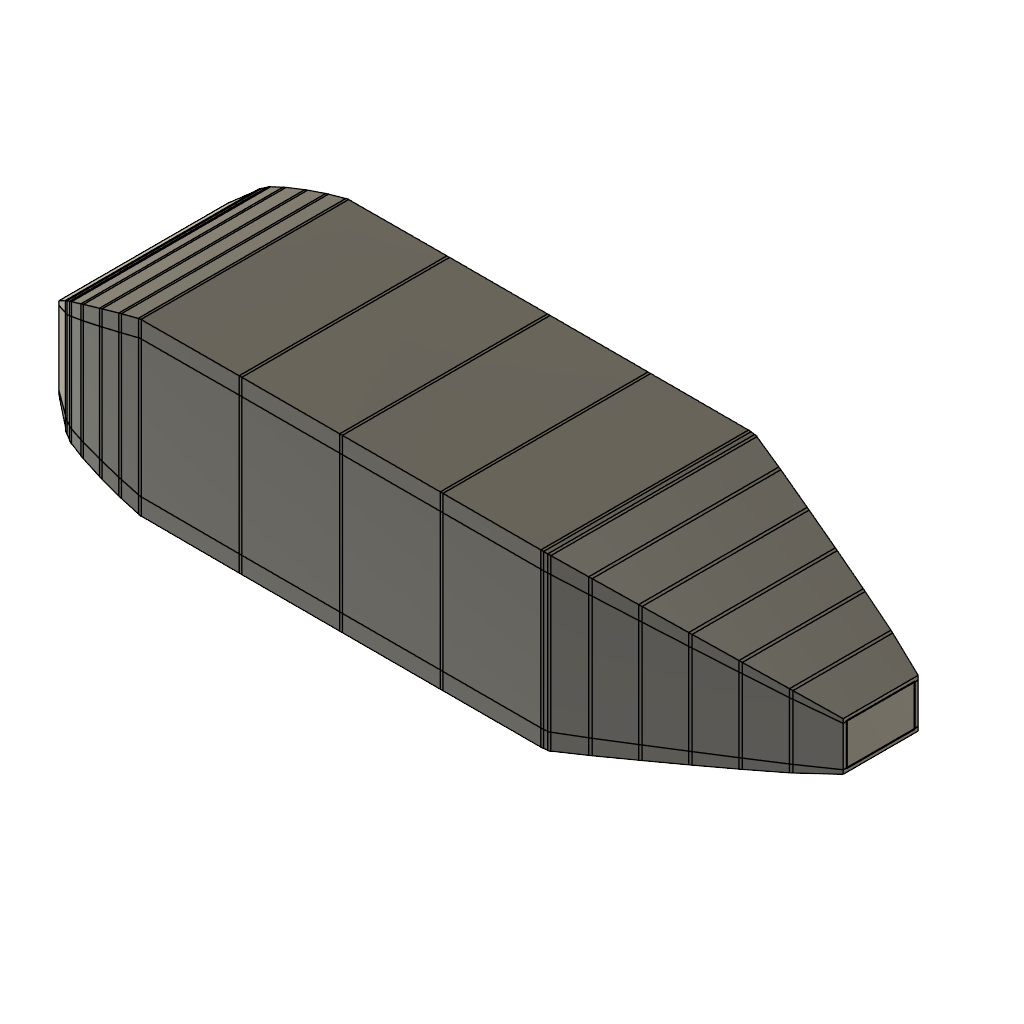
Magnetide-B-full (Autodesk Fusion 360 design; units mm, degrees)
part number: 2026-10-21-01-34-00-853
Autodesk Fusion 360 part; units mm, degrees
(part 1 of 3)
ref_plane "WorkPlane1" through (60, 0, 0) normal (1, 0, 0) x (0, 1, 0)
sketch "plate_a" plane through (60, 0, 0) normal (1, 0, 0) x (0, 0, -1)
  line L0 (-7, -21.85) -> (-7, 21.85)
  line L1 (-7, 21.85) -> (-10.5, 21.85)
  line L2 (-10.5, 21.85) -> (-10.5, 22.75)
  line L3 (-10.5, 22.75) -> (-7, 22.75)
  line L4 (-7, 22.75) -> (-7, 23.5)
  line L5 (-7, 23.5) -> (-18.5, 23.5)
  line L6 (-18.5, 23.5) -> (-18.5, 20.3)
  line L7 (-18.5, 20.3) -> (-8.5, 20.3)
  line L8 (-8.5, 20.3) -> (-8.5, -20.3)
  line L9 (-8.5, -20.3) -> (-18.5, -20.3)
  line L10 (-18.5, -20.3) -> (-18.5, -23.5)
  line L11 (-18.5, -23.5) -> (-7, -23.5)
  line L12 (-7, -23.5) -> (-7, -22.75)
  line L13 (-7, -22.75) -> (-10.5, -22.75)
  line L14 (-10.5, -22.75) -> (-10.5, -21.85)
  line L15 (-10.5, -21.85) -> (-7, -21.85)
extrude "Extrude1" add sketch "plate_a" along normal mid plane 120 makes body 1
ref_plane "WorkPlane2" through (60, 0, 0) normal (1, 0, 0) x (0, 1, 0)
sketch "plate_b" plane through (60, 0, 0) normal (1, 0, 0) x (0, 0, -1)
  line L0 (7, -21.85) -> (7, 21.85)
  line L1 (7, 21.85) -> (10.5, 21.85)
  line L2 (10.5, 21.85) -> (10.5, 22.75)
  line L3 (10.5, 22.75) -> (7, 22.75)
  line L4 (7, 22.75) -> (7, 23.5)
  line L5 (7, 23.5) -> (18.5, 23.5)
  line L6 (18.5, 23.5) -> (18.5, 20.3)
  line L7 (18.5, 20.3) -> (8.5, 20.3)
  line L8 (8.5, 20.3) -> (8.5, -20.3)
  line L9 (8.5, -20.3) -> (18.5, -20.3)
  line L10 (18.5, -20.3) -> (18.5, -23.5)
  line L11 (18.5, -23.5) -> (7, -23.5)
  line L12 (7, -23.5) -> (7, -22.75)
  line L13 (7, -22.75) -> (10.5, -22.75)
  line L14 (10.5, -22.75) -> (10.5, -21.85)
  line L15 (10.5, -21.85) -> (7, -21.85)
extrude "Extrude2" add sketch "plate_b" along normal mid plane 120 separate body makes body 2
ref_plane "WorkPlane3" through (0, -22.7, 0) normal (0, 1, 0) x (0, 0, 1)
sketch "rail_left" plane through (0, -22.7, 0) normal (0, 1, 0) x (1, 0, 0)
  line L0 (0, 7) -> (120, 7)
  line L1 (120, 7) -> (120, -7)
  line L2 (120, -7) -> (0, -7)
  line L3 (0, -7) -> (0, 7)
extrude "Extrude3" add sketch "rail_left" along normal mid plane 1.6 separate body makes body 3
ref_plane "WorkPlane4" through (0, 22.7, 0) normal (0, 1, 0) x (0, 0, 1)
sketch "rail_right" plane through (0, 22.7, 0) normal (0, 1, 0) x (1, 0, 0)
  line L0 (0, 7) -> (120, 7)
  line L1 (120, 7) -> (120, -7)
  line L2 (120, -7) -> (0, -7)
  line L3 (0, -7) -> (0, 7)
extrude "Extrude4" add sketch "rail_right" along normal mid plane 1.6 separate body makes body 4
ref_plane "WorkPlane5" through (-20, 0, 0) normal (1, 0, 0) x (0, 1, 0)
sketch "Sketch5" plane through (-20, 0, 0) normal (1, 0, 0) x (0, 0, -1)
  line L0 (-12, -23.5) -> (-10.5, -23.5)
  line L1 (-10.5, -23.5) -> (-10.5, 23.5)
  line L2 (-10.5, 23.5) -> (-12, 23.5)
  line L3 (-12, 23.5) -> (-12, -23.5)
ref_plane "WorkPlane6" through (-15.6, 0, 0) normal (1, 0, 0) x (0, 1, 0)
sketch "Sketch6" plane through (-15.6, 0, 0) normal (1, 0, 0) x (0, 0, -1)
  line L0 (-10.6294, -23.5) -> (-9.1294, -23.5)
  line L1 (-9.1294, -23.5) -> (-9.1294, 23.5)
  line L2 (-9.1294, 23.5) -> (-10.6294, 23.5)
  line L3 (-10.6294, 23.5) -> (-10.6294, -23.5)
loft "Loft1" add profiles "Sketch5", "Sketch6" section 1 section 2 separate body makes body 5
ref_plane "WorkPlane7" through (-16.4, 0, 0) normal (1, 0, 0) x (0, 1, 0)
sketch "Sketch7" plane through (-16.4, 0, 0) normal (1, 0, 0) x (0, 0, -1)
  line L0 (-10.8534, -23.5) -> (-9.3534, -23.5)
  line L1 (-9.3534, -23.5) -> (-9.3534, 23.5)
  line L2 (-9.3534, 23.5) -> (-10.8534, 23.5)
  line L3 (-10.8534, 23.5) -> (-10.8534, -23.5)
ref_plane "WorkPlane8" through (-11.6, 0, 0) normal (1, 0, 0) x (0, 1, 0)
sketch "Sketch8" plane through (-11.6, 0, 0) normal (1, 0, 0) x (0, 0, -1)
  line L0 (-9.6774, -23.5) -> (-8.1774, -23.5)
  line L1 (-8.1774, -23.5) -> (-8.1774, 23.5)
  line L2 (-8.1774, 23.5) -> (-9.6774, 23.5)
  line L3 (-9.6774, 23.5) -> (-9.6774, -23.5)
loft "Loft2" add profiles "Sketch7", "Sketch8" section 1 section 2 separate body makes body 6
ref_plane "WorkPlane9" through (-12.4, 0, 0) normal (1, 0, 0) x (0, 1, 0)
sketch "Sketch9" plane through (-12.4, 0, 0) normal (1, 0, 0) x (0, 0, -1)
  line L0 (-9.8454, -23.5) -> (-8.3454, -23.5)
  line L1 (-8.3454, -23.5) -> (-8.3454, 23.5)
  line L2 (-8.3454, 23.5) -> (-9.8454, 23.5)
  line L3 (-9.8454, 23.5) -> (-9.8454, -23.5)
ref_plane "WorkPlane10" through (-7.6, 0, 0) normal (1, 0, 0) x (0, 1, 0)
sketch "Sketch10" plane through (-7.6, 0, 0) normal (1, 0, 0) x (0, 0, -1)
  line L0 (-9.0054, -23.5) -> (-7.5054, -23.5)
  line L1 (-7.5054, -23.5) -> (-7.5054, 23.5)
  line L2 (-7.5054, 23.5) -> (-9.0054, 23.5)
  line L3 (-9.0054, 23.5) -> (-9.0054, -23.5)
loft "Loft3" add profiles "Sketch9", "Sketch10" section 1 section 2 separate body makes body 7
ref_plane "WorkPlane11" through (-8.4, 0, 0) normal (1, 0, 0) x (0, 1, 0)
sketch "Sketch11" plane through (-8.4, 0, 0) normal (1, 0, 0) x (0, 0, -1)
  line L0 (-9.1174, -23.5) -> (-7.6174, -23.5)
  line L1 (-7.6174, -23.5) -> (-7.6174, 23.5)
  line L2 (-7.6174, 23.5) -> (-9.1174, 23.5)
  line L3 (-9.1174, 23.5) -> (-9.1174, -23.5)
ref_plane "WorkPlane12" through (-3.6, 0, 0) normal (1, 0, 0) x (0, 1, 0)
sketch "Sketch12" plane through (-3.6, 0, 0) normal (1, 0, 0) x (0, 0, -1)
  line L0 (-8.6134, -23.5) -> (-7.1134, -23.5)
  line L1 (-7.1134, -23.5) -> (-7.1134, 23.5)
  line L2 (-7.1134, 23.5) -> (-8.6134, 23.5)
  line L3 (-8.6134, 23.5) -> (-8.6134, -23.5)
loft "Loft4" add profiles "Sketch11", "Sketch12" section 1 section 2 separate body makes body 8
ref_plane "WorkPlane13" through (-4.4, 0, 0) normal (1, 0, 0) x (0, 1, 0)
sketch "Sketch13" plane through (-4.4, 0, 0) normal (1, 0, 0) x (0, 0, -1)
  line L0 (-8.6694, -23.5) -> (-7.1694, -23.5)
  line L1 (-7.1694, -23.5) -> (-7.1694, 23.5)
  line L2 (-7.1694, 23.5) -> (-8.6694, 23.5)
  line L3 (-8.6694, 23.5) -> (-8.6694, -23.5)
ref_plane "WorkPlane14" through (0, 0, 0) normal (1, 0, 0) x (0, 1, 0)
sketch "Sketch14" plane through (0, 0, 0) normal (1, 0, 0) x (0, 0, -1)
  line L0 (-8.5, -23.5) -> (-7, -23.5)
  line L1 (-7, -23.5) -> (-7, 23.5)
  line L2 (-7, 23.5) -> (-8.5, 23.5)
  line L3 (-8.5, 23.5) -> (-8.5, -23.5)
loft "Loft5" add profiles "Sketch13", "Sketch14" section 1 section 2 separate body makes body 9
ref_plane "WorkPlane15" through (-20, 0, 0) normal (1, 0, 0) x (0, 1, 0)
sketch "Sketch15" plane through (-20, 0, 0) normal (1, 0, 0) x (0, 0, -1)
  line L0 (10.5, -23.5) -> (12, -23.5)
  line L1 (12, -23.5) -> (12, 23.5)
  line L2 (12, 23.5) -> (10.5, 23.5)
  line L3 (10.5, 23.5) -> (10.5, -23.5)
ref_plane "WorkPlane16" through (-15.6, 0, 0) normal (1, 0, 0) x (0, 1, 0)
sketch "Sketch16" plane through (-15.6, 0, 0) normal (1, 0, 0) x (0, 0, -1)
  line L0 (9.1294, -23.5) -> (10.6294, -23.5)
  line L1 (10.6294, -23.5) -> (10.6294, 23.5)
  line L2 (10.6294, 23.5) -> (9.1294, 23.5)
  line L3 (9.1294, 23.5) -> (9.1294, -23.5)
loft "Loft6" add profiles "Sketch15", "Sketch16" section 1 section 2 separate body makes body 10
ref_plane "WorkPlane17" through (-16.4, 0, 0) normal (1, 0, 0) x (0, 1, 0)
sketch "Sketch17" plane through (-16.4, 0, 0) normal (1, 0, 0) x (0, 0, -1)
  line L0 (9.3534, -23.5) -> (10.8534, -23.5)
  line L1 (10.8534, -23.5) -> (10.8534, 23.5)
  line L2 (10.8534, 23.5) -> (9.3534, 23.5)
  line L3 (9.3534, 23.5) -> (9.3534, -23.5)
ref_plane "WorkPlane18" through (-11.6, 0, 0) normal (1, 0, 0) x (0, 1, 0)
sketch "Sketch18" plane through (-11.6, 0, 0) normal (1, 0, 0) x (0, 0, -1)
  line L0 (8.1774, -23.5) -> (9.6774, -23.5)
  line L1 (9.6774, -23.5) -> (9.6774, 23.5)
  line L2 (9.6774, 23.5) -> (8.1774, 23.5)
  line L3 (8.1774, 23.5) -> (8.1774, -23.5)
loft "Loft7" add profiles "Sketch17", "Sketch18" section 1 section 2 separate body makes body 11
ref_plane "WorkPlane19" through (-12.4, 0, 0) normal (1, 0, 0) x (0, 1, 0)
sketch "Sketch19" plane through (-12.4, 0, 0) normal (1, 0, 0) x (0, 0, -1)
  line L0 (8.3454, -23.5) -> (9.8454, -23.5)
  line L1 (9.8454, -23.5) -> (9.8454, 23.5)
  line L2 (9.8454, 23.5) -> (8.3454, 23.5)
  line L3 (8.3454, 23.5) -> (8.3454, -23.5)
ref_plane "WorkPlane20" through (-7.6, 0, 0) normal (1, 0, 0) x (0, 1, 0)
sketch "Sketch20" plane through (-7.6, 0, 0) normal (1, 0, 0) x (0, 0, -1)
  line L0 (7.5054, -23.5) -> (9.0054, -23.5)
  line L1 (9.0054, -23.5) -> (9.0054, 23.5)
  line L2 (9.0054, 23.5) -> (7.5054, 23.5)
  line L3 (7.5054, 23.5) -> (7.5054, -23.5)
loft "Loft8" add profiles "Sketch19", "Sketch20" section 1 section 2 separate body makes body 12
ref_plane "WorkPlane21" through (-8.4, 0, 0) normal (1, 0, 0) x (0, 1, 0)
sketch "Sketch21" plane through (-8.4, 0, 0) normal (1, 0, 0) x (0, 0, -1)
  line L0 (7.6174, -23.5) -> (9.1174, -23.5)
  line L1 (9.1174, -23.5) -> (9.1174, 23.5)
  line L2 (9.1174, 23.5) -> (7.6174, 23.5)
  line L3 (7.6174, 23.5) -> (7.6174, -23.5)
ref_plane "WorkPlane22" through (-3.6, 0, 0) normal (1, 0, 0) x (0, 1, 0)
sketch "Sketch22" plane through (-3.6, 0, 0) normal (1, 0, 0) x (0, 0, -1)
  line L0 (7.1134, -23.5) -> (8.6134, -23.5)
  line L1 (8.6134, -23.5) -> (8.6134, 23.5)
  line L2 (8.6134, 23.5) -> (7.1134, 23.5)
  line L3 (7.1134, 23.5) -> (7.1134, -23.5)
loft "Loft9" add profiles "Sketch21", "Sketch22" section 1 section 2 separate body makes body 13
ref_plane "WorkPlane23" through (-4.4, 0, 0) normal (1, 0, 0) x (0, 1, 0)
sketch "Sketch23" plane through (-4.4, 0, 0) normal (1, 0, 0) x (0, 0, -1)
  line L0 (7.1694, -23.5) -> (8.6694, -23.5)
  line L1 (8.6694, -23.5) -> (8.6694, 23.5)
  line L2 (8.6694, 23.5) -> (7.1694, 23.5)
  line L3 (7.1694, 23.5) -> (7.1694, -23.5)
ref_plane "WorkPlane24" through (0, 0, 0) normal (1, 0, 0) x (0, 1, 0)
sketch "Sketch24" plane through (0, 0, 0) normal (1, 0, 0) x (0, 0, -1)
  line L0 (7, -23.5) -> (8.5, -23.5)
  line L1 (8.5, -23.5) -> (8.5, 23.5)
  line L2 (8.5, 23.5) -> (7, 23.5)
  line L3 (7, 23.5) -> (7, -23.5)
loft "Loft10" add profiles "Sketch23", "Sketch24" section 1 section 2 separate body makes body 14
ref_plane "WorkPlane25" through (-20, 0, 0) normal (1, 0, 0) x (0, 1, 0)
sketch "Sketch25" plane through (-20, 0, 0) normal (1, 0, 0) x (0, 0, -1)
  line L0 (-10.5, -23.5) -> (10.5, -23.5)
  line L1 (10.5, -23.5) -> (10.5, -21.5)
  line L2 (10.5, -21.5) -> (-10.5, -21.5)
  line L3 (-10.5, -21.5) -> (-10.5, -23.5)
ref_plane "WorkPlane26" through (-15.6, 0, 0) normal (1, 0, 0) x (0, 1, 0)
sketch "Sketch26" plane through (-15.6, 0, 0) normal (1, 0, 0) x (0, 0, -1)
  line L0 (-9.1294, -23.5) -> (9.1294, -23.5)
  line L1 (9.1294, -23.5) -> (9.1294, -21.5)
  line L2 (9.1294, -21.5) -> (-9.1294, -21.5)
  line L3 (-9.1294, -21.5) -> (-9.1294, -23.5)
loft "Loft11" add profiles "Sketch25", "Sketch26" section 1 section 2 separate body makes body 15
ref_plane "WorkPlane27" through (-16.4, 0, 0) normal (1, 0, 0) x (0, 1, 0)
sketch "Sketch27" plane through (-16.4, 0, 0) normal (1, 0, 0) x (0, 0, -1)
  line L0 (-9.3534, -23.5) -> (9.3534, -23.5)
  line L1 (9.3534, -23.5) -> (9.3534, -21.5)
  line L2 (9.3534, -21.5) -> (-9.3534, -21.5)
  line L3 (-9.3534, -21.5) -> (-9.3534, -23.5)
ref_plane "WorkPlane28" through (-11.6, 0, 0) normal (1, 0, 0) x (0, 1, 0)
sketch "Sketch28" plane through (-11.6, 0, 0) normal (1, 0, 0) x (0, 0, -1)
  line L0 (-8.1774, -23.5) -> (8.1774, -23.5)
  line L1 (8.1774, -23.5) -> (8.1774, -21.5)
  line L2 (8.1774, -21.5) -> (-8.1774, -21.5)
  line L3 (-8.1774, -21.5) -> (-8.1774, -23.5)
loft "Loft12" add profiles "Sketch27", "Sketch28" section 1 section 2 separate body makes body 16
ref_plane "WorkPlane29" through (-12.4, 0, 0) normal (1, 0, 0) x (0, 1, 0)
sketch "Sketch29" plane through (-12.4, 0, 0) normal (1, 0, 0) x (0, 0, -1)
  line L0 (-8.3454, -23.5) -> (8.3454, -23.5)
  line L1 (8.3454, -23.5) -> (8.3454, -21.5)
  line L2 (8.3454, -21.5) -> (-8.3454, -21.5)
  line L3 (-8.3454, -21.5) -> (-8.3454, -23.5)
ref_plane "WorkPlane30" through (-7.6, 0, 0) normal (1, 0, 0) x (0, 1, 0)
sketch "Sketch30" plane through (-7.6, 0, 0) normal (1, 0, 0) x (0, 0, -1)
  line L0 (-7.5054, -23.5) -> (7.5054, -23.5)
  line L1 (7.5054, -23.5) -> (7.5054, -21.5)
  line L2 (7.5054, -21.5) -> (-7.5054, -21.5)
  line L3 (-7.5054, -21.5) -> (-7.5054, -23.5)
loft "Loft13" add profiles "Sketch29", "Sketch30" section 1 section 2 separate body makes body 17
ref_plane "WorkPlane31" through (-8.4, 0, 0) normal (1, 0, 0) x (0, 1, 0)
sketch "Sketch31" plane through (-8.4, 0, 0) normal (1, 0, 0) x (0, 0, -1)
  line L0 (-7.6174, -23.5) -> (7.6174, -23.5)
  line L1 (7.6174, -23.5) -> (7.6174, -21.5)
  line L2 (7.6174, -21.5) -> (-7.6174, -21.5)
  line L3 (-7.6174, -21.5) -> (-7.6174, -23.5)
ref_plane "WorkPlane32" through (-3.6, 0, 0) normal (1, 0, 0) x (0, 1, 0)
sketch "Sketch32" plane through (-3.6, 0, 0) normal (1, 0, 0) x (0, 0, -1)
  line L0 (-7.1134, -23.5) -> (7.1134, -23.5)
  line L1 (7.1134, -23.5) -> (7.1134, -21.5)
  line L2 (7.1134, -21.5) -> (-7.1134, -21.5)
  line L3 (-7.1134, -21.5) -> (-7.1134, -23.5)
loft "Loft14" add profiles "Sketch31", "Sketch32" section 1 section 2 separate body makes body 18
ref_plane "WorkPlane33" through (-4.4, 0, 0) normal (1, 0, 0) x (0, 1, 0)
sketch "Sketch33" plane through (-4.4, 0, 0) normal (1, 0, 0) x (0, 0, -1)
  line L0 (-7.1694, -23.5) -> (7.1694, -23.5)
  line L1 (7.1694, -23.5) -> (7.1694, -21.5)
  line L2 (7.1694, -21.5) -> (-7.1694, -21.5)
  line L3 (-7.1694, -21.5) -> (-7.1694, -23.5)
ref_plane "WorkPlane34" through (0, 0, 0) normal (1, 0, 0) x (0, 1, 0)
sketch "Sketch34" plane through (0, 0, 0) normal (1, 0, 0) x (0, 0, -1)
  line L0 (-7, -23.5) -> (7, -23.5)
  line L1 (7, -23.5) -> (7, -21.5)
  line L2 (7, -21.5) -> (-7, -21.5)
  line L3 (-7, -21.5) -> (-7, -23.5)
loft "Loft15" add profiles "Sketch33", "Sketch34" section 1 section 2 separate body makes body 19
ref_plane "WorkPlane35" through (-20, 0, 0) normal (1, 0, 0) x (0, 1, 0)
sketch "Sketch35" plane through (-20, 0, 0) normal (1, 0, 0) x (0, 0, -1)
  line L0 (-10.5, 21.5) -> (10.5, 21.5)
  line L1 (10.5, 21.5) -> (10.5, 23.5)
  line L2 (10.5, 23.5) -> (-10.5, 23.5)
  line L3 (-10.5, 23.5) -> (-10.5, 21.5)
ref_plane "WorkPlane36" through (-15.6, 0, 0) normal (1, 0, 0) x (0, 1, 0)
sketch "Sketch36" plane through (-15.6, 0, 0) normal (1, 0, 0) x (0, 0, -1)
  line L0 (-9.1294, 21.5) -> (9.1294, 21.5)
  line L1 (9.1294, 21.5) -> (9.1294, 23.5)
  line L2 (9.1294, 23.5) -> (-9.1294, 23.5)
  line L3 (-9.1294, 23.5) -> (-9.1294, 21.5)
loft "Loft16" add profiles "Sketch35", "Sketch36" section 1 section 2 separate body makes body 20
ref_plane "WorkPlane37" through (-16.4, 0, 0) normal (1, 0, 0) x (0, 1, 0)
sketch "Sketch37" plane through (-16.4, 0, 0) normal (1, 0, 0) x (0, 0, -1)
  line L0 (-9.3534, 21.5) -> (9.3534, 21.5)
  line L1 (9.3534, 21.5) -> (9.3534, 23.5)
  line L2 (9.3534, 23.5) -> (-9.3534, 23.5)
  line L3 (-9.3534, 23.5) -> (-9.3534, 21.5)
ref_plane "WorkPlane38" through (-11.6, 0, 0) normal (1, 0, 0) x (0, 1, 0)
sketch "Sketch38" plane through (-11.6, 0, 0) normal (1, 0, 0) x (0, 0, -1)
  line L0 (-8.1774, 21.5) -> (8.1774, 21.5)
  line L1 (8.1774, 21.5) -> (8.1774, 23.5)
  line L2 (8.1774, 23.5) -> (-8.1774, 23.5)
  line L3 (-8.1774, 23.5) -> (-8.1774, 21.5)
loft "Loft17" add profiles "Sketch37", "Sketch38" section 1 section 2 separate body makes body 21
ref_plane "WorkPlane39" through (-12.4, 0, 0) normal (1, 0, 0) x (0, 1, 0)
sketch "Sketch39" plane through (-12.4, 0, 0) normal (1, 0, 0) x (0, 0, -1)
  line L0 (-8.3454, 21.5) -> (8.3454, 21.5)
  line L1 (8.3454, 21.5) -> (8.3454, 23.5)
  line L2 (8.3454, 23.5) -> (-8.3454, 23.5)
  line L3 (-8.3454, 23.5) -> (-8.3454, 21.5)
ref_plane "WorkPlane40" through (-7.6, 0, 0) normal (1, 0, 0) x (0, 1, 0)
sketch "Sketch40" plane through (-7.6, 0, 0) normal (1, 0, 0) x (0, 0, -1)
  line L0 (-7.5054, 21.5) -> (7.5054, 21.5)
  line L1 (7.5054, 21.5) -> (7.5054, 23.5)
  line L2 (7.5054, 23.5) -> (-7.5054, 23.5)
  line L3 (-7.5054, 23.5) -> (-7.5054, 21.5)
loft "Loft18" add profiles "Sketch39", "Sketch40" section 1 section 2 separate body makes body 22
ref_plane "WorkPlane41" through (-8.4, 0, 0) normal (1, 0, 0) x (0, 1, 0)
sketch "Sketch41" plane through (-8.4, 0, 0) normal (1, 0, 0) x (0, 0, -1)
  line L0 (-7.6174, 21.5) -> (7.6174, 21.5)
  line L1 (7.6174, 21.5) -> (7.6174, 23.5)
  line L2 (7.6174, 23.5) -> (-7.6174, 23.5)
  line L3 (-7.6174, 23.5) -> (-7.6174, 21.5)
ref_plane "WorkPlane42" through (-3.6, 0, 0) normal (1, 0, 0) x (0, 1, 0)
sketch "Sketch42" plane through (-3.6, 0, 0) normal (1, 0, 0) x (0, 0, -1)
  line L0 (-7.1134, 21.5) -> (7.1134, 21.5)
  line L1 (7.1134, 21.5) -> (7.1134, 23.5)
  line L2 (7.1134, 23.5) -> (-7.1134, 23.5)
  line L3 (-7.1134, 23.5) -> (-7.1134, 21.5)
loft "Loft19" add profiles "Sketch41", "Sketch42" section 1 section 2 separate body makes body 23
ref_plane "WorkPlane43" through (-4.4, 0, 0) normal (1, 0, 0) x (0, 1, 0)
sketch "Sketch43" plane through (-4.4, 0, 0) normal (1, 0, 0) x (0, 0, -1)
  line L0 (-7.1694, 21.5) -> (7.1694, 21.5)
  line L1 (7.1694, 21.5) -> (7.1694, 23.5)
  line L2 (7.1694, 23.5) -> (-7.1694, 23.5)
  line L3 (-7.1694, 23.5) -> (-7.1694, 21.5)
ref_plane "WorkPlane44" through (0, 0, 0) normal (1, 0, 0) x (0, 1, 0)
sketch "Sketch44" plane through (0, 0, 0) normal (1, 0, 0) x (0, 0, -1)
  line L0 (-7, 21.5) -> (7, 21.5)
  line L1 (7, 21.5) -> (7, 23.5)
  line L2 (7, 23.5) -> (-7, 23.5)
  line L3 (-7, 23.5) -> (-7, 21.5)
loft "Loft20" add profiles "Sketch43", "Sketch44" section 1 section 2 separate body makes body 24
ref_plane "WorkPlane45" through (-21, 0, 0) normal (1, 0, 0) x (0, 1, 0)
sketch "front_flange" plane through (-21, 0, 0) normal (1, 0, 0) x (0, 0, -1)
  line L0 (-14, -25.5) -> (14, -25.5)
  line L1 (14, -25.5) -> (14, 25.5)
  line L2 (14, 25.5) -> (-14, 25.5)
  line L3 (-14, 25.5) -> (-14, -25.5)
  line L4 (-10.5, -23.5) -> (-10.5, 23.5)
  line L5 (-10.5, 23.5) -> (10.5, 23.5)
  line L6 (10.5, 23.5) -> (10.5, -23.5)
  line L7 (10.5, -23.5) -> (-10.5, -23.5)
extrude "Extrude5" add sketch "front_flange" along normal mid plane 2 separate body makes body 25
ref_plane "WorkPlane46" through (121, 0, 0) normal (1, 0, 0) x (0, 1, 0)
sketch "rear_cap" plane through (121, 0, 0) normal (1, 0, 0) x (0, 0, -1)
  line L0 (-18.4, -25.5) -> (18.4, -25.5)
  line L1 (18.4, -25.5) -> (18.4, 25.5)
  line L2 (18.4, 25.5) -> (-18.4, 25.5)
  line L3 (-18.4, 25.5) -> (-18.4, -25.5)
  line L4 (-10.6, -23.6) -> (10.6, -23.6)
  line L5 (10.6, -23.6) -> (10.6, 23.6)
  line L6 (10.6, 23.6) -> (-10.6, 23.6)
  line L7 (-10.6, 23.6) -> (-10.6, -23.6)
extrude "Extrude6" add sketch "rear_cap" along normal mid plane 2 separate body makes body 26
ref_plane "WorkPlane47" through (0, -20.75, 0) normal (0, 1, 0) x (0, 0, 1)
sketch "graphite_left" plane through (0, -20.75, 0) normal (0, 1, 0) x (1, 0, 0)
  line L0 (-5, -7) -> (120, -7)
  line L1 (120, -7) -> (120, 7)
  line L2 (120, 7) -> (-5, 7)
  line L3 (-5, 7) -> (-5, -7)
extrude "Extrude7" add sketch "graphite_left" along normal mid plane 1.5 separate body makes body 27
ref_plane "WorkPlane48" through (0, 20.75, 0) normal (0, 1, 0) x (0, 0, 1)
sketch "graphite_right" plane through (0, 20.75, 0) normal (0, 1, 0) x (1, 0, 0)
  line L0 (-5, -7) -> (120, -7)
  line L1 (120, -7) -> (120, 7)
  line L2 (120, 7) -> (-5, 7)
  line L3 (-5, 7) -> (-5, -7)
extrude "Extrude8" add sketch "graphite_right" along normal mid plane 1.5 separate body makes body 28
ref_plane "WorkPlane49" through (0, 0, 11) normal (0, 0, 1) x (1, 0, 0)
sketch "magnet_N_st0_a0_d0" plane through (0, 0, 11) normal (0, 0, 1) x (1, 0, 0)
  line L0 (0.2, -20) -> (19.8, -20)
  line L1 (19.8, -20) -> (19.8, -10)
  line L2 (19.8, -10) -> (0.2, -10)
  line L3 (0.2, -10) -> (0.2, -20)
extrude "Extrude9" add sketch "magnet_N_st0_a0_d0" along normal mid plane 5 separate body makes body 29
ref_plane "WorkPlane50" through (0, 0, 16) normal (0, 0, 1) x (1, 0, 0)
sketch "magnet_N_st0_a0_d1" plane through (0, 0, 16) normal (0, 0, 1) x (1, 0, 0)
  line L0 (0.2, -20) -> (19.8, -20)
  line L1 (19.8, -20) -> (19.8, -10)
  line L2 (19.8, -10) -> (0.2, -10)
  line L3 (0.2, -10) -> (0.2, -20)
extrude "Extrude10" add sketch "magnet_N_st0_a0_d1" along normal mid plane 5 separate body makes body 30
ref_plane "WorkPlane51" through (0, 0, -11) normal (0, 0, 1) x (1, 0, 0)
sketch "magnet_S_st0_a0_d0" plane through (0, 0, -11) normal (0, 0, 1) x (1, 0, 0)
  line L0 (0.2, -20) -> (19.8, -20)
  line L1 (19.8, -20) -> (19.8, -10)
  line L2 (19.8, -10) -> (0.2, -10)
  line L3 (0.2, -10) -> (0.2, -20)
extrude "Extrude11" add sketch "magnet_S_st0_a0_d0" along normal mid plane 5 separate body makes body 31
ref_plane "WorkPlane52" through (0, 0, -16) normal (0, 0, 1) x (1, 0, 0)
sketch "magnet_S_st0_a0_d1" plane through (0, 0, -16) normal (0, 0, 1) x (1, 0, 0)
  line L0 (0.2, -20) -> (19.8, -20)
  line L1 (19.8, -20) -> (19.8, -10)
  line L2 (19.8, -10) -> (0.2, -10)
  line L3 (0.2, -10) -> (0.2, -20)
extrude "Extrude12" add sketch "magnet_S_st0_a0_d1" along normal mid plane 5 separate body makes body 32
ref_plane "WorkPlane53" through (0, 0, 11) normal (0, 0, 1) x (1, 0, 0)
sketch "magnet_N_st0_a1_d0" plane through (0, 0, 11) normal (0, 0, 1) x (1, 0, 0)
  line L0 (0.2, -10) -> (19.8, -10)
  line L1 (19.8, -10) -> (19.8, 0)
  line L2 (19.8, 0) -> (0.2, 0)
  line L3 (0.2, 0) -> (0.2, -10)
extrude "Extrude13" add sketch "magnet_N_st0_a1_d0" along normal mid plane 5 separate body makes body 33
ref_plane "WorkPlane54" through (0, 0, 16) normal (0, 0, 1) x (1, 0, 0)
sketch "magnet_N_st0_a1_d1" plane through (0, 0, 16) normal (0, 0, 1) x (1, 0, 0)
  line L0 (0.2, -10) -> (19.8, -10)
  line L1 (19.8, -10) -> (19.8, 0)
  line L2 (19.8, 0) -> (0.2, 0)
  line L3 (0.2, 0) -> (0.2, -10)
extrude "Extrude14" add sketch "magnet_N_st0_a1_d1" along normal mid plane 5 separate body makes body 34
ref_plane "WorkPlane55" through (0, 0, -11) normal (0, 0, 1) x (1, 0, 0)
sketch "magnet_S_st0_a1_d0" plane through (0, 0, -11) normal (0, 0, 1) x (1, 0, 0)
  line L0 (0.2, -10) -> (19.8, -10)
  line L1 (19.8, -10) -> (19.8, 0)
  line L2 (19.8, 0) -> (0.2, 0)
  line L3 (0.2, 0) -> (0.2, -10)
extrude "Extrude15" add sketch "magnet_S_st0_a1_d0" along normal mid plane 5 separate body makes body 35
ref_plane "WorkPlane56" through (0, 0, -16) normal (0, 0, 1) x (1, 0, 0)
sketch "magnet_S_st0_a1_d1" plane through (0, 0, -16) normal (0, 0, 1) x (1, 0, 0)
  line L0 (0.2, -10) -> (19.8, -10)
  line L1 (19.8, -10) -> (19.8, 0)
  line L2 (19.8, 0) -> (0.2, 0)
  line L3 (0.2, 0) -> (0.2, -10)
extrude "Extrude16" add sketch "magnet_S_st0_a1_d1" along normal mid plane 5 separate body makes body 36
ref_plane "WorkPlane57" through (0, 0, 11) normal (0, 0, 1) x (1, 0, 0)
sketch "magnet_N_st0_a2_d0" plane through (0, 0, 11) normal (0, 0, 1) x (1, 0, 0)
  line L0 (0.2, 0) -> (19.8, 0)
  line L1 (19.8, 0) -> (19.8, 10)
  line L2 (19.8, 10) -> (0.2, 10)
  line L3 (0.2, 10) -> (0.2, 0)
extrude "Extrude17" add sketch "magnet_N_st0_a2_d0" along normal mid plane 5 separate body makes body 37
ref_plane "WorkPlane58" through (0, 0, 16) normal (0, 0, 1) x (1, 0, 0)
sketch "magnet_N_st0_a2_d1" plane through (0, 0, 16) normal (0, 0, 1) x (1, 0, 0)
  line L0 (0.2, 0) -> (19.8, 0)
  line L1 (19.8, 0) -> (19.8, 10)
  line L2 (19.8, 10) -> (0.2, 10)
  line L3 (0.2, 10) -> (0.2, 0)
extrude "Extrude18" add sketch "magnet_N_st0_a2_d1" along normal mid plane 5 separate body makes body 38
ref_plane "WorkPlane59" through (0, 0, -11) normal (0, 0, 1) x (1, 0, 0)
sketch "magnet_S_st0_a2_d0" plane through (0, 0, -11) normal (0, 0, 1) x (1, 0, 0)
  line L0 (0.2, 0) -> (19.8, 0)
  line L1 (19.8, 0) -> (19.8, 10)
  line L2 (19.8, 10) -> (0.2, 10)
  line L3 (0.2, 10) -> (0.2, 0)
extrude "Extrude19" add sketch "magnet_S_st0_a2_d0" along normal mid plane 5 separate body makes body 39
ref_plane "WorkPlane60" through (0, 0, -16) normal (0, 0, 1) x (1, 0, 0)
sketch "magnet_S_st0_a2_d1" plane through (0, 0, -16) normal (0, 0, 1) x (1, 0, 0)
  line L0 (0.2, 0) -> (19.8, 0)
  line L1 (19.8, 0) -> (19.8, 10)
  line L2 (19.8, 10) -> (0.2, 10)
  line L3 (0.2, 10) -> (0.2, 0)
extrude "Extrude20" add sketch "magnet_S_st0_a2_d1" along normal mid plane 5 separate body makes body 40
ref_plane "WorkPlane61" through (0, 0, 11) normal (0, 0, 1) x (1, 0, 0)
sketch "magnet_N_st0_a3_d0" plane through (0, 0, 11) normal (0, 0, 1) x (1, 0, 0)
  line L0 (0.2, 10) -> (19.8, 10)
  line L1 (19.8, 10) -> (19.8, 20)
  line L2 (19.8, 20) -> (0.2, 20)
  line L3 (0.2, 20) -> (0.2, 10)
extrude "Extrude21" add sketch "magnet_N_st0_a3_d0" along normal mid plane 5 separate body makes body 41
ref_plane "WorkPlane62" through (0, 0, 16) normal (0, 0, 1) x (1, 0, 0)
sketch "magnet_N_st0_a3_d1" plane through (0, 0, 16) normal (0, 0, 1) x (1, 0, 0)
  line L0 (0.2, 10) -> (19.8, 10)
  line L1 (19.8, 10) -> (19.8, 20)
  line L2 (19.8, 20) -> (0.2, 20)
  line L3 (0.2, 20) -> (0.2, 10)
extrude "Extrude22" add sketch "magnet_N_st0_a3_d1" along normal mid plane 5 separate body makes body 42
ref_plane "WorkPlane63" through (0, 0, -11) normal (0, 0, 1) x (1, 0, 0)
sketch "magnet_S_st0_a3_d0" plane through (0, 0, -11) normal (0, 0, 1) x (1, 0, 0)
  line L0 (0.2, 10) -> (19.8, 10)
  line L1 (19.8, 10) -> (19.8, 20)
  line L2 (19.8, 20) -> (0.2, 20)
  line L3 (0.2, 20) -> (0.2, 10)
extrude "Extrude23" add sketch "magnet_S_st0_a3_d0" along normal mid plane 5 separate body makes body 43
ref_plane "WorkPlane64" through (0, 0, -16) normal (0, 0, 1) x (1, 0, 0)
sketch "magnet_S_st0_a3_d1" plane through (0, 0, -16) normal (0, 0, 1) x (1, 0, 0)
  line L0 (0.2, 10) -> (19.8, 10)
  line L1 (19.8, 10) -> (19.8, 20)
  line L2 (19.8, 20) -> (0.2, 20)
  line L3 (0.2, 20) -> (0.2, 10)
extrude "Extrude24" add sketch "magnet_S_st0_a3_d1" along normal mid plane 5 separate body makes body 44
ref_plane "WorkPlane65" through (0, 0, 11) normal (0, 0, 1) x (1, 0, 0)
sketch "magnet_N_st1_a0_d0" plane through (0, 0, 11) normal (0, 0, 1) x (1, 0, 0)
  line L0 (20.2, -20) -> (39.8, -20)
  line L1 (39.8, -20) -> (39.8, -10)
  line L2 (39.8, -10) -> (20.2, -10)
  line L3 (20.2, -10) -> (20.2, -20)
extrude "Extrude25" add sketch "magnet_N_st1_a0_d0" along normal mid plane 5 separate body makes body 45
ref_plane "WorkPlane66" through (0, 0, 16) normal (0, 0, 1) x (1, 0, 0)
sketch "magnet_N_st1_a0_d1" plane through (0, 0, 16) normal (0, 0, 1) x (1, 0, 0)
  line L0 (20.2, -20) -> (39.8, -20)
  line L1 (39.8, -20) -> (39.8, -10)
  line L2 (39.8, -10) -> (20.2, -10)
  line L3 (20.2, -10) -> (20.2, -20)
extrude "Extrude26" add sketch "magnet_N_st1_a0_d1" along normal mid plane 5 separate body makes body 46
ref_plane "WorkPlane67" through (0, 0, -11) normal (0, 0, 1) x (1, 0, 0)
sketch "magnet_S_st1_a0_d0" plane through (0, 0, -11) normal (0, 0, 1) x (1, 0, 0)
  line L0 (20.2, -20) -> (39.8, -20)
  line L1 (39.8, -20) -> (39.8, -10)
  line L2 (39.8, -10) -> (20.2, -10)
  line L3 (20.2, -10) -> (20.2, -20)
extrude "Extrude27" add sketch "magnet_S_st1_a0_d0" along normal mid plane 5 separate body makes body 47
ref_plane "WorkPlane68" through (0, 0, -16) normal (0, 0, 1) x (1, 0, 0)
sketch "magnet_S_st1_a0_d1" plane through (0, 0, -16) normal (0, 0, 1) x (1, 0, 0)
  line L0 (20.2, -20) -> (39.8, -20)
  line L1 (39.8, -20) -> (39.8, -10)
  line L2 (39.8, -10) -> (20.2, -10)
  line L3 (20.2, -10) -> (20.2, -20)
extrude "Extrude28" add sketch "magnet_S_st1_a0_d1" along normal mid plane 5 separate body makes body 48
ref_plane "WorkPlane69" through (0, 0, 11) normal (0, 0, 1) x (1, 0, 0)
sketch "magnet_N_st1_a1_d0" plane through (0, 0, 11) normal (0, 0, 1) x (1, 0, 0)
  line L0 (20.2, -10) -> (39.8, -10)
  line L1 (39.8, -10) -> (39.8, 0)
  line L2 (39.8, 0) -> (20.2, 0)
  line L3 (20.2, 0) -> (20.2, -10)
extrude "Extrude29" add sketch "magnet_N_st1_a1_d0" along normal mid plane 5 separate body makes body 49
ref_plane "WorkPlane70" through (0, 0, 16) normal (0, 0, 1) x (1, 0, 0)
sketch "magnet_N_st1_a1_d1" plane through (0, 0, 16) normal (0, 0, 1) x (1, 0, 0)
  line L0 (20.2, -10) -> (39.8, -10)
  line L1 (39.8, -10) -> (39.8, 0)
  line L2 (39.8, 0) -> (20.2, 0)
  line L3 (20.2, 0) -> (20.2, -10)
extrude "Extrude30" add sketch "magnet_N_st1_a1_d1" along normal mid plane 5 separate body makes body 50
ref_plane "WorkPlane71" through (0, 0, -11) normal (0, 0, 1) x (1, 0, 0)
sketch "magnet_S_st1_a1_d0" plane through (0, 0, -11) normal (0, 0, 1) x (1, 0, 0)
  line L0 (20.2, -10) -> (39.8, -10)
  line L1 (39.8, -10) -> (39.8, 0)
  line L2 (39.8, 0) -> (20.2, 0)
  line L3 (20.2, 0) -> (20.2, -10)
extrude "Extrude31" add sketch "magnet_S_st1_a1_d0" along normal mid plane 5 separate body makes body 51
ref_plane "WorkPlane72" through (0, 0, -16) normal (0, 0, 1) x (1, 0, 0)
sketch "magnet_S_st1_a1_d1" plane through (0, 0, -16) normal (0, 0, 1) x (1, 0, 0)
  line L0 (20.2, -10) -> (39.8, -10)
  line L1 (39.8, -10) -> (39.8, 0)
  line L2 (39.8, 0) -> (20.2, 0)
  line L3 (20.2, 0) -> (20.2, -10)
extrude "Extrude32" add sketch "magnet_S_st1_a1_d1" along normal mid plane 5 separate body makes body 52
ref_plane "WorkPlane73" through (0, 0, 11) normal (0, 0, 1) x (1, 0, 0)
sketch "magnet_N_st1_a2_d0" plane through (0, 0, 11) normal (0, 0, 1) x (1, 0, 0)
  line L0 (20.2, 0) -> (39.8, 0)
  line L1 (39.8, 0) -> (39.8, 10)
  line L2 (39.8, 10) -> (20.2, 10)
  line L3 (20.2, 10) -> (20.2, 0)
extrude "Extrude33" add sketch "magnet_N_st1_a2_d0" along normal mid plane 5 separate body makes body 53
ref_plane "WorkPlane74" through (0, 0, 16) normal (0, 0, 1) x (1, 0, 0)
sketch "magnet_N_st1_a2_d1" plane through (0, 0, 16) normal (0, 0, 1) x (1, 0, 0)
  line L0 (20.2, 0) -> (39.8, 0)
  line L1 (39.8, 0) -> (39.8, 10)
  line L2 (39.8, 10) -> (20.2, 10)
  line L3 (20.2, 10) -> (20.2, 0)
extrude "Extrude34" add sketch "magnet_N_st1_a2_d1" along normal mid plane 5 separate body makes body 54
ref_plane "WorkPlane75" through (0, 0, -11) normal (0, 0, 1) x (1, 0, 0)
sketch "magnet_S_st1_a2_d0" plane through (0, 0, -11) normal (0, 0, 1) x (1, 0, 0)
  line L0 (20.2, 0) -> (39.8, 0)
  line L1 (39.8, 0) -> (39.8, 10)
  line L2 (39.8, 10) -> (20.2, 10)
  line L3 (20.2, 10) -> (20.2, 0)
extrude "Extrude35" add sketch "magnet_S_st1_a2_d0" along normal mid plane 5 separate body makes body 55
ref_plane "WorkPlane76" through (0, 0, -16) normal (0, 0, 1) x (1, 0, 0)
sketch "magnet_S_st1_a2_d1" plane through (0, 0, -16) normal (0, 0, 1) x (1, 0, 0)
  line L0 (20.2, 0) -> (39.8, 0)
  line L1 (39.8, 0) -> (39.8, 10)
  line L2 (39.8, 10) -> (20.2, 10)
  line L3 (20.2, 10) -> (20.2, 0)
extrude "Extrude36" add sketch "magnet_S_st1_a2_d1" along normal mid plane 5 separate body makes body 56
ref_plane "WorkPlane77" through (0, 0, 11) normal (0, 0, 1) x (1, 0, 0)
sketch "magnet_N_st1_a3_d0" plane through (0, 0, 11) normal (0, 0, 1) x (1, 0, 0)
  line L0 (20.2, 10) -> (39.8, 10)
  line L1 (39.8, 10) -> (39.8, 20)
  line L2 (39.8, 20) -> (20.2, 20)
  line L3 (20.2, 20) -> (20.2, 10)
extrude "Extrude37" add sketch "magnet_N_st1_a3_d0" along normal mid plane 5 separate body makes body 57
ref_plane "WorkPlane78" through (0, 0, 16) normal (0, 0, 1) x (1, 0, 0)
sketch "magnet_N_st1_a3_d1" plane through (0, 0, 16) normal (0, 0, 1) x (1, 0, 0)
  line L0 (20.2, 10) -> (39.8, 10)
  line L1 (39.8, 10) -> (39.8, 20)
  line L2 (39.8, 20) -> (20.2, 20)
  line L3 (20.2, 20) -> (20.2, 10)
extrude "Extrude38" add sketch "magnet_N_st1_a3_d1" along normal mid plane 5 separate body makes body 58
ref_plane "WorkPlane79" through (0, 0, -11) normal (0, 0, 1) x (1, 0, 0)
sketch "magnet_S_st1_a3_d0" plane through (0, 0, -11) normal (0, 0, 1) x (1, 0, 0)
  line L0 (20.2, 10) -> (39.8, 10)
  line L1 (39.8, 10) -> (39.8, 20)
  line L2 (39.8, 20) -> (20.2, 20)
  line L3 (20.2, 20) -> (20.2, 10)
extrude "Extrude39" add sketch "magnet_S_st1_a3_d0" along normal mid plane 5 separate body makes body 59
ref_plane "WorkPlane80" through (0, 0, -16) normal (0, 0, 1) x (1, 0, 0)
sketch "magnet_S_st1_a3_d1" plane through (0, 0, -16) normal (0, 0, 1) x (1, 0, 0)
  line L0 (20.2, 10) -> (39.8, 10)
  line L1 (39.8, 10) -> (39.8, 20)
  line L2 (39.8, 20) -> (20.2, 20)
  line L3 (20.2, 20) -> (20.2, 10)
extrude "Extrude40" add sketch "magnet_S_st1_a3_d1" along normal mid plane 5 separate body makes body 60
ref_plane "WorkPlane81" through (0, 0, 11) normal (0, 0, 1) x (1, 0, 0)
sketch "magnet_N_st2_a0_d0" plane through (0, 0, 11) normal (0, 0, 1) x (1, 0, 0)
  line L0 (40.2, -20) -> (59.8, -20)
  line L1 (59.8, -20) -> (59.8, -10)
  line L2 (59.8, -10) -> (40.2, -10)
  line L3 (40.2, -10) -> (40.2, -20)
extrude "Extrude41" add sketch "magnet_N_st2_a0_d0" along normal mid plane 5 separate body makes body 61
ref_plane "WorkPlane82" through (0, 0, 16) normal (0, 0, 1) x (1, 0, 0)
sketch "magnet_N_st2_a0_d1" plane through (0, 0, 16) normal (0, 0, 1) x (1, 0, 0)
  line L0 (40.2, -20) -> (59.8, -20)
  line L1 (59.8, -20) -> (59.8, -10)
  line L2 (59.8, -10) -> (40.2, -10)
  line L3 (40.2, -10) -> (40.2, -20)
extrude "Extrude42" add sketch "magnet_N_st2_a0_d1" along normal mid plane 5 separate body makes body 62
ref_plane "WorkPlane83" through (0, 0, -11) normal (0, 0, 1) x (1, 0, 0)
sketch "magnet_S_st2_a0_d0" plane through (0, 0, -11) normal (0, 0, 1) x (1, 0, 0)
  line L0 (40.2, -20) -> (59.8, -20)
  line L1 (59.8, -20) -> (59.8, -10)
  line L2 (59.8, -10) -> (40.2, -10)
  line L3 (40.2, -10) -> (40.2, -20)
extrude "Extrude43" add sketch "magnet_S_st2_a0_d0" along normal mid plane 5 separate body makes body 63
ref_plane "WorkPlane84" through (0, 0, -16) normal (0, 0, 1) x (1, 0, 0)
sketch "magnet_S_st2_a0_d1" plane through (0, 0, -16) normal (0, 0, 1) x (1, 0, 0)
  line L0 (40.2, -20) -> (59.8, -20)
  line L1 (59.8, -20) -> (59.8, -10)
  line L2 (59.8, -10) -> (40.2, -10)
  line L3 (40.2, -10) -> (40.2, -20)
extrude "Extrude44" add sketch "magnet_S_st2_a0_d1" along normal mid plane 5 separate body makes body 64
ref_plane "WorkPlane85" through (0, 0, 11) normal (0, 0, 1) x (1, 0, 0)
sketch "magnet_N_st2_a1_d0" plane through (0, 0, 11) normal (0, 0, 1) x (1, 0, 0)
  line L0 (40.2, -10) -> (59.8, -10)
  line L1 (59.8, -10) -> (59.8, 0)
  line L2 (59.8, 0) -> (40.2, 0)
  line L3 (40.2, 0) -> (40.2, -10)
extrude "Extrude45" add sketch "magnet_N_st2_a1_d0" along normal mid plane 5 separate body makes body 65
ref_plane "WorkPlane86" through (0, 0, 16) normal (0, 0, 1) x (1, 0, 0)
sketch "magnet_N_st2_a1_d1" plane through (0, 0, 16) normal (0, 0, 1) x (1, 0, 0)
  line L0 (40.2, -10) -> (59.8, -10)
  line L1 (59.8, -10) -> (59.8, 0)
  line L2 (59.8, 0) -> (40.2, 0)
  line L3 (40.2, 0) -> (40.2, -10)
extrude "Extrude46" add sketch "magnet_N_st2_a1_d1" along normal mid plane 5 separate body makes body 66
ref_plane "WorkPlane87" through (0, 0, -11) normal (0, 0, 1) x (1, 0, 0)
sketch "magnet_S_st2_a1_d0" plane through (0, 0, -11) normal (0, 0, 1) x (1, 0, 0)
  line L0 (40.2, -10) -> (59.8, -10)
  line L1 (59.8, -10) -> (59.8, 0)
  line L2 (59.8, 0) -> (40.2, 0)
  line L3 (40.2, 0) -> (40.2, -10)
extrude "Extrude47" add sketch "magnet_S_st2_a1_d0" along normal mid plane 5 separate body makes body 67
ref_plane "WorkPlane88" through (0, 0, -16) normal (0, 0, 1) x (1, 0, 0)
sketch "magnet_S_st2_a1_d1" plane through (0, 0, -16) normal (0, 0, 1) x (1, 0, 0)
  line L0 (40.2, -10) -> (59.8, -10)
  line L1 (59.8, -10) -> (59.8, 0)
  line L2 (59.8, 0) -> (40.2, 0)
  line L3 (40.2, 0) -> (40.2, -10)
extrude "Extrude48" add sketch "magnet_S_st2_a1_d1" along normal mid plane 5 separate body makes body 68
ref_plane "WorkPlane89" through (0, 0, 11) normal (0, 0, 1) x (1, 0, 0)
sketch "magnet_N_st2_a2_d0" plane through (0, 0, 11) normal (0, 0, 1) x (1, 0, 0)
  line L0 (40.2, 0) -> (59.8, 0)
  line L1 (59.8, 0) -> (59.8, 10)
  line L2 (59.8, 10) -> (40.2, 10)
  line L3 (40.2, 10) -> (40.2, 0)
extrude "Extrude49" add sketch "magnet_N_st2_a2_d0" along normal mid plane 5 separate body makes body 69
ref_plane "WorkPlane90" through (0, 0, 16) normal (0, 0, 1) x (1, 0, 0)
sketch "magnet_N_st2_a2_d1" plane through (0, 0, 16) normal (0, 0, 1) x (1, 0, 0)
  line L0 (40.2, 0) -> (59.8, 0)
  line L1 (59.8, 0) -> (59.8, 10)
  line L2 (59.8, 10) -> (40.2, 10)
  line L3 (40.2, 10) -> (40.2, 0)
extrude "Extrude50" add sketch "magnet_N_st2_a2_d1" along normal mid plane 5 separate body makes body 70
ref_plane "WorkPlane91" through (0, 0, -11) normal (0, 0, 1) x (1, 0, 0)
sketch "magnet_S_st2_a2_d0" plane through (0, 0, -11) normal (0, 0, 1) x (1, 0, 0)
  line L0 (40.2, 0) -> (59.8, 0)
  line L1 (59.8, 0) -> (59.8, 10)
  line L2 (59.8, 10) -> (40.2, 10)
  line L3 (40.2, 10) -> (40.2, 0)
extrude "Extrude51" add sketch "magnet_S_st2_a2_d0" along normal mid plane 5 separate body makes body 71
ref_plane "WorkPlane92" through (0, 0, -16) normal (0, 0, 1) x (1, 0, 0)
sketch "magnet_S_st2_a2_d1" plane through (0, 0, -16) normal (0, 0, 1) x (1, 0, 0)
  line L0 (40.2, 0) -> (59.8, 0)
  line L1 (59.8, 0) -> (59.8, 10)
  line L2 (59.8, 10) -> (40.2, 10)
  line L3 (40.2, 10) -> (40.2, 0)
extrude "Extrude52" add sketch "magnet_S_st2_a2_d1" along normal mid plane 5 separate body makes body 72
ref_plane "WorkPlane93" through (0, 0, 11) normal (0, 0, 1) x (1, 0, 0)
sketch "magnet_N_st2_a3_d0" plane through (0, 0, 11) normal (0, 0, 1) x (1, 0, 0)
  line L0 (40.2, 10) -> (59.8, 10)
  line L1 (59.8, 10) -> (59.8, 20)
  line L2 (59.8, 20) -> (40.2, 20)
  line L3 (40.2, 20) -> (40.2, 10)
extrude "Extrude53" add sketch "magnet_N_st2_a3_d0" along normal mid plane 5 separate body makes body 73
ref_plane "WorkPlane94" through (0, 0, 16) normal (0, 0, 1) x (1, 0, 0)
sketch "magnet_N_st2_a3_d1" plane through (0, 0, 16) normal (0, 0, 1) x (1, 0, 0)
  line L0 (40.2, 10) -> (59.8, 10)
  line L1 (59.8, 10) -> (59.8, 20)
  line L2 (59.8, 20) -> (40.2, 20)
  line L3 (40.2, 20) -> (40.2, 10)
extrude "Extrude54" add sketch "magnet_N_st2_a3_d1" along normal mid plane 5 separate body makes body 74
ref_plane "WorkPlane95" through (0, 0, -11) normal (0, 0, 1) x (1, 0, 0)
sketch "magnet_S_st2_a3_d0" plane through (0, 0, -11) normal (0, 0, 1) x (1, 0, 0)
  line L0 (40.2, 10) -> (59.8, 10)
  line L1 (59.8, 10) -> (59.8, 20)
  line L2 (59.8, 20) -> (40.2, 20)
  line L3 (40.2, 20) -> (40.2, 10)
extrude "Extrude55" add sketch "magnet_S_st2_a3_d0" along normal mid plane 5 separate body makes body 75
ref_plane "WorkPlane96" through (0, 0, -16) normal (0, 0, 1) x (1, 0, 0)
sketch "magnet_S_st2_a3_d1" plane through (0, 0, -16) normal (0, 0, 1) x (1, 0, 0)
  line L0 (40.2, 10) -> (59.8, 10)
  line L1 (59.8, 10) -> (59.8, 20)
  line L2 (59.8, 20) -> (40.2, 20)
  line L3 (40.2, 20) -> (40.2, 10)
extrude "Extrude56" add sketch "magnet_S_st2_a3_d1" along normal mid plane 5 separate body makes body 76
ref_plane "WorkPlane97" through (0, 0, 11) normal (0, 0, 1) x (1, 0, 0)
sketch "magnet_N_st3_a0_d0" plane through (0, 0, 11) normal (0, 0, 1) x (1, 0, 0)
  line L0 (60.2, -20) -> (79.8, -20)
  line L1 (79.8, -20) -> (79.8, -10)
  line L2 (79.8, -10) -> (60.2, -10)
  line L3 (60.2, -10) -> (60.2, -20)
extrude "Extrude57" add sketch "magnet_N_st3_a0_d0" along normal mid plane 5 separate body makes body 77
ref_plane "WorkPlane98" through (0, 0, 16) normal (0, 0, 1) x (1, 0, 0)
sketch "magnet_N_st3_a0_d1" plane through (0, 0, 16) normal (0, 0, 1) x (1, 0, 0)
  line L0 (60.2, -20) -> (79.8, -20)
  line L1 (79.8, -20) -> (79.8, -10)
  line L2 (79.8, -10) -> (60.2, -10)
  line L3 (60.2, -10) -> (60.2, -20)
extrude "Extrude58" add sketch "magnet_N_st3_a0_d1" along normal mid plane 5 separate body makes body 78
ref_plane "WorkPlane99" through (0, 0, -11) normal (0, 0, 1) x (1, 0, 0)
sketch "magnet_S_st3_a0_d0" plane through (0, 0, -11) normal (0, 0, 1) x (1, 0, 0)
  line L0 (60.2, -20) -> (79.8, -20)
  line L1 (79.8, -20) -> (79.8, -10)
  line L2 (79.8, -10) -> (60.2, -10)
  line L3 (60.2, -10) -> (60.2, -20)
extrude "Extrude59" add sketch "magnet_S_st3_a0_d0" along normal mid plane 5 separate body makes body 79
ref_plane "WorkPlane100" through (0, 0, -16) normal (0, 0, 1) x (1, 0, 0)
sketch "magnet_S_st3_a0_d1" plane through (0, 0, -16) normal (0, 0, 1) x (1, 0, 0)
  line L0 (60.2, -20) -> (79.8, -20)
  line L1 (79.8, -20) -> (79.8, -10)
  line L2 (79.8, -10) -> (60.2, -10)
  line L3 (60.2, -10) -> (60.2, -20)
extrude "Extrude60" add sketch "magnet_S_st3_a0_d1" along normal mid plane 5 separate body makes body 80
ref_plane "WorkPlane101" through (0, 0, 11) normal (0, 0, 1) x (1, 0, 0)
sketch "magnet_N_st3_a1_d0" plane through (0, 0, 11) normal (0, 0, 1) x (1, 0, 0)
  line L0 (60.2, -10) -> (79.8, -10)
  line L1 (79.8, -10) -> (79.8, 0)
  line L2 (79.8, 0) -> (60.2, 0)
  line L3 (60.2, 0) -> (60.2, -10)
extrude "Extrude61" add sketch "magnet_N_st3_a1_d0" along normal mid plane 5 separate body makes body 81
ref_plane "WorkPlane102" through (0, 0, 16) normal (0, 0, 1) x (1, 0, 0)
sketch "magnet_N_st3_a1_d1" plane through (0, 0, 16) normal (0, 0, 1) x (1, 0, 0)
  line L0 (60.2, -10) -> (79.8, -10)
  line L1 (79.8, -10) -> (79.8, 0)
  line L2 (79.8, 0) -> (60.2, 0)
  line L3 (60.2, 0) -> (60.2, -10)
extrude "Extrude62" add sketch "magnet_N_st3_a1_d1" along normal mid plane 5 separate body makes body 82
ref_plane "WorkPlane103" through (0, 0, -11) normal (0, 0, 1) x (1, 0, 0)
sketch "magnet_S_st3_a1_d0" plane through (0, 0, -11) normal (0, 0, 1) x (1, 0, 0)
  line L0 (60.2, -10) -> (79.8, -10)
  line L1 (79.8, -10) -> (79.8, 0)
  line L2 (79.8, 0) -> (60.2, 0)
  line L3 (60.2, 0) -> (60.2, -10)
extrude "Extrude63" add sketch "magnet_S_st3_a1_d0" along normal mid plane 5 separate body makes body 83
ref_plane "WorkPlane104" through (0, 0, -16) normal (0, 0, 1) x (1, 0, 0)
sketch "magnet_S_st3_a1_d1" plane through (0, 0, -16) normal (0, 0, 1) x (1, 0, 0)
  line L0 (60.2, -10) -> (79.8, -10)
  line L1 (79.8, -10) -> (79.8, 0)
  line L2 (79.8, 0) -> (60.2, 0)
  line L3 (60.2, 0) -> (60.2, -10)
extrude "Extrude64" add sketch "magnet_S_st3_a1_d1" along normal mid plane 5 separate body makes body 84
ref_plane "WorkPlane105" through (0, 0, 11) normal (0, 0, 1) x (1, 0, 0)
sketch "magnet_N_st3_a2_d0" plane through (0, 0, 11) normal (0, 0, 1) x (1, 0, 0)
  line L0 (60.2, 0) -> (79.8, 0)
  line L1 (79.8, 0) -> (79.8, 10)
  line L2 (79.8, 10) -> (60.2, 10)
  line L3 (60.2, 10) -> (60.2, 0)
extrude "Extrude65" add sketch "magnet_N_st3_a2_d0" along normal mid plane 5 separate body makes body 85
ref_plane "WorkPlane106" through (0, 0, 16) normal (0, 0, 1) x (1, 0, 0)
sketch "magnet_N_st3_a2_d1" plane through (0, 0, 16) normal (0, 0, 1) x (1, 0, 0)
  line L0 (60.2, 0) -> (79.8, 0)
  line L1 (79.8, 0) -> (79.8, 10)
  line L2 (79.8, 10) -> (60.2, 10)
  line L3 (60.2, 10) -> (60.2, 0)
extrude "Extrude66" add sketch "magnet_N_st3_a2_d1" along normal mid plane 5 separate body makes body 86
ref_plane "WorkPlane107" through (0, 0, -11) normal (0, 0, 1) x (1, 0, 0)
sketch "magnet_S_st3_a2_d0" plane through (0, 0, -11) normal (0, 0, 1) x (1, 0, 0)
  line L0 (60.2, 0) -> (79.8, 0)
  line L1 (79.8, 0) -> (79.8, 10)
  line L2 (79.8, 10) -> (60.2, 10)
  line L3 (60.2, 10) -> (60.2, 0)
extrude "Extrude67" add sketch "magnet_S_st3_a2_d0" along normal mid plane 5 separate body makes body 87
ref_plane "WorkPlane108" through (0, 0, -16) normal (0, 0, 1) x (1, 0, 0)
sketch "magnet_S_st3_a2_d1" plane through (0, 0, -16) normal (0, 0, 1) x (1, 0, 0)
  line L0 (60.2, 0) -> (79.8, 0)
  line L1 (79.8, 0) -> (79.8, 10)
  line L2 (79.8, 10) -> (60.2, 10)
  line L3 (60.2, 10) -> (60.2, 0)
extrude "Extrude68" add sketch "magnet_S_st3_a2_d1" along normal mid plane 5 separate body makes body 88
ref_plane "WorkPlane109" through (0, 0, 11) normal (0, 0, 1) x (1, 0, 0)
sketch "magnet_N_st3_a3_d0" plane through (0, 0, 11) normal (0, 0, 1) x (1, 0, 0)
  line L0 (60.2, 10) -> (79.8, 10)
  line L1 (79.8, 10) -> (79.8, 20)
  line L2 (79.8, 20) -> (60.2, 20)
  line L3 (60.2, 20) -> (60.2, 10)
extrude "Extrude69" add sketch "magnet_N_st3_a3_d0" along normal mid plane 5 separate body makes body 89
ref_plane "WorkPlane110" through (0, 0, 16) normal (0, 0, 1) x (1, 0, 0)
sketch "magnet_N_st3_a3_d1" plane through (0, 0, 16) normal (0, 0, 1) x (1, 0, 0)
  line L0 (60.2, 10) -> (79.8, 10)
  line L1 (79.8, 10) -> (79.8, 20)
  line L2 (79.8, 20) -> (60.2, 20)
  line L3 (60.2, 20) -> (60.2, 10)
extrude "Extrude70" add sketch "magnet_N_st3_a3_d1" along normal mid plane 5 separate body makes body 90
ref_plane "WorkPlane111" through (0, 0, -11) normal (0, 0, 1) x (1, 0, 0)
sketch "magnet_S_st3_a3_d0" plane through (0, 0, -11) normal (0, 0, 1) x (1, 0, 0)
  line L0 (60.2, 10) -> (79.8, 10)
  line L1 (79.8, 10) -> (79.8, 20)
  line L2 (79.8, 20) -> (60.2, 20)
  line L3 (60.2, 20) -> (60.2, 10)
extrude "Extrude71" add sketch "magnet_S_st3_a3_d0" along normal mid plane 5 separate body makes body 91
ref_plane "WorkPlane112" through (0, 0, -16) normal (0, 0, 1) x (1, 0, 0)
sketch "magnet_S_st3_a3_d1" plane through (0, 0, -16) normal (0, 0, 1) x (1, 0, 0)
  line L0 (60.2, 10) -> (79.8, 10)
  line L1 (79.8, 10) -> (79.8, 20)
  line L2 (79.8, 20) -> (60.2, 20)
  line L3 (60.2, 20) -> (60.2, 10)
extrude "Extrude72" add sketch "magnet_S_st3_a3_d1" along normal mid plane 5 separate body makes body 92
ref_plane "WorkPlane113" through (0, 0, 11) normal (0, 0, 1) x (1, 0, 0)
sketch "magnet_N_st4_a0_d0" plane through (0, 0, 11) normal (0, 0, 1) x (1, 0, 0)
  line L0 (80.2, -20) -> (99.8, -20)
  line L1 (99.8, -20) -> (99.8, -10)
  line L2 (99.8, -10) -> (80.2, -10)
  line L3 (80.2, -10) -> (80.2, -20)
extrude "Extrude73" add sketch "magnet_N_st4_a0_d0" along normal mid plane 5 separate body makes body 93
ref_plane "WorkPlane114" through (0, 0, 16) normal (0, 0, 1) x (1, 0, 0)
sketch "magnet_N_st4_a0_d1" plane through (0, 0, 16) normal (0, 0, 1) x (1, 0, 0)
  line L0 (80.2, -20) -> (99.8, -20)
  line L1 (99.8, -20) -> (99.8, -10)
  line L2 (99.8, -10) -> (80.2, -10)
  line L3 (80.2, -10) -> (80.2, -20)
extrude "Extrude74" add sketch "magnet_N_st4_a0_d1" along normal mid plane 5 separate body makes body 94
ref_plane "WorkPlane115" through (0, 0, -11) normal (0, 0, 1) x (1, 0, 0)
sketch "magnet_S_st4_a0_d0" plane through (0, 0, -11) normal (0, 0, 1) x (1, 0, 0)
  line L0 (80.2, -20) -> (99.8, -20)
  line L1 (99.8, -20) -> (99.8, -10)
  line L2 (99.8, -10) -> (80.2, -10)
  line L3 (80.2, -10) -> (80.2, -20)
extrude "Extrude75" add sketch "magnet_S_st4_a0_d0" along normal mid plane 5 separate body makes body 95
ref_plane "WorkPlane116" through (0, 0, -16) normal (0, 0, 1) x (1, 0, 0)
sketch "magnet_S_st4_a0_d1" plane through (0, 0, -16) normal (0, 0, 1) x (1, 0, 0)
  line L0 (80.2, -20) -> (99.8, -20)
  line L1 (99.8, -20) -> (99.8, -10)
  line L2 (99.8, -10) -> (80.2, -10)
  line L3 (80.2, -10) -> (80.2, -20)
extrude "Extrude76" add sketch "magnet_S_st4_a0_d1" along normal mid plane 5 separate body makes body 96
ref_plane "WorkPlane117" through (0, 0, 11) normal (0, 0, 1) x (1, 0, 0)
sketch "magnet_N_st4_a1_d0" plane through (0, 0, 11) normal (0, 0, 1) x (1, 0, 0)
  line L0 (80.2, -10) -> (99.8, -10)
  line L1 (99.8, -10) -> (99.8, 0)
  line L2 (99.8, 0) -> (80.2, 0)
  line L3 (80.2, 0) -> (80.2, -10)
extrude "Extrude77" add sketch "magnet_N_st4_a1_d0" along normal mid plane 5 separate body makes body 97
ref_plane "WorkPlane118" through (0, 0, 16) normal (0, 0, 1) x (1, 0, 0)
sketch "magnet_N_st4_a1_d1" plane through (0, 0, 16) normal (0, 0, 1) x (1, 0, 0)
  line L0 (80.2, -10) -> (99.8, -10)
  line L1 (99.8, -10) -> (99.8, 0)
  line L2 (99.8, 0) -> (80.2, 0)
  line L3 (80.2, 0) -> (80.2, -10)
extrude "Extrude78" add sketch "magnet_N_st4_a1_d1" along normal mid plane 5 separate body makes body 98
ref_plane "WorkPlane119" through (0, 0, -11) normal (0, 0, 1) x (1, 0, 0)
sketch "magnet_S_st4_a1_d0" plane through (0, 0, -11) normal (0, 0, 1) x (1, 0, 0)
  line L0 (80.2, -10) -> (99.8, -10)
  line L1 (99.8, -10) -> (99.8, 0)
  line L2 (99.8, 0) -> (80.2, 0)
  line L3 (80.2, 0) -> (80.2, -10)
extrude "Extrude79" add sketch "magnet_S_st4_a1_d0" along normal mid plane 5 separate body makes body 99
ref_plane "WorkPlane120" through (0, 0, -16) normal (0, 0, 1) x (1, 0, 0)
sketch "magnet_S_st4_a1_d1" plane through (0, 0, -16) normal (0, 0, 1) x (1, 0, 0)
  line L0 (80.2, -10) -> (99.8, -10)
  line L1 (99.8, -10) -> (99.8, 0)
  line L2 (99.8, 0) -> (80.2, 0)
  line L3 (80.2, 0) -> (80.2, -10)
extrude "Extrude80" add sketch "magnet_S_st4_a1_d1" along normal mid plane 5 separate body makes body 100
ref_plane "WorkPlane121" through (0, 0, 11) normal (0, 0, 1) x (1, 0, 0)
sketch "magnet_N_st4_a2_d0" plane through (0, 0, 11) normal (0, 0, 1) x (1, 0, 0)
  line L0 (80.2, 0) -> (99.8, 0)
  line L1 (99.8, 0) -> (99.8, 10)
  line L2 (99.8, 10) -> (80.2, 10)
  line L3 (80.2, 10) -> (80.2, 0)
extrude "Extrude81" add sketch "magnet_N_st4_a2_d0" along normal mid plane 5 separate body makes body 101
ref_plane "WorkPlane122" through (0, 0, 16) normal (0, 0, 1) x (1, 0, 0)
sketch "magnet_N_st4_a2_d1" plane through (0, 0, 16) normal (0, 0, 1) x (1, 0, 0)
  line L0 (80.2, 0) -> (99.8, 0)
  line L1 (99.8, 0) -> (99.8, 10)
  line L2 (99.8, 10) -> (80.2, 10)
  line L3 (80.2, 10) -> (80.2, 0)
extrude "Extrude82" add sketch "magnet_N_st4_a2_d1" along normal mid plane 5 separate body makes body 102
ref_plane "WorkPlane123" through (0, 0, -11) normal (0, 0, 1) x (1, 0, 0)
sketch "magnet_S_st4_a2_d0" plane through (0, 0, -11) normal (0, 0, 1) x (1, 0, 0)
  line L0 (80.2, 0) -> (99.8, 0)
  line L1 (99.8, 0) -> (99.8, 10)
  line L2 (99.8, 10) -> (80.2, 10)
  line L3 (80.2, 10) -> (80.2, 0)
extrude "Extrude83" add sketch "magnet_S_st4_a2_d0" along normal mid plane 5 separate body makes body 103
ref_plane "WorkPlane124" through (0, 0, -16) normal (0, 0, 1) x (1, 0, 0)
sketch "magnet_S_st4_a2_d1" plane through (0, 0, -16) normal (0, 0, 1) x (1, 0, 0)
  line L0 (80.2, 0) -> (99.8, 0)
  line L1 (99.8, 0) -> (99.8, 10)
  line L2 (99.8, 10) -> (80.2, 10)
  line L3 (80.2, 10) -> (80.2, 0)
extrude "Extrude84" add sketch "magnet_S_st4_a2_d1" along normal mid plane 5 separate body makes body 104